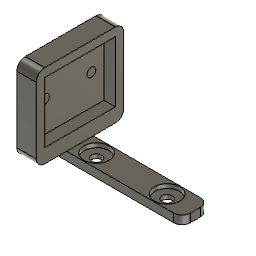
cctvAqara (Autodesk Fusion 360 design; units mm, degrees)
part number: 2026-08-10-19-56-16-923
Autodesk Fusion 360 part; units mm, degrees
sketch "Sketch1" plane through (0, 0, 0) normal (0, 0, 1) x (1, 0, 0)
  line L0 (-28, 37) -> (62, 37)
  line L1 (62, 37) -> (62, 18)
  line L2 (62, 18) -> (-28, 18)
  line L3 (-28, 18) -> (-28, 37)
  dimension "d1" = 90
  dimension "d2" = 19
  constraint horizontal L0
  constraint vertical L1
  constraint horizontal L2
  constraint vertical L3
  measures "d1" distance of L0.start L0.end
  measures "d2" distance of L0.start L2.end
extrude "Extrude1" add sketch "Sketch1" along normal blind 6 makes body 1
sketch "Sketch2" plane through (0, 0, 6) normal (0, 0, 1) x (-1, 0, 0)
  line L0 (28, -37) -> (28, -18)
  line L1 (28, -18) -> (-62, -18)
  line L2 (-62, -18) -> (-62, -37)
  line L3 (-62, -37) -> (28, -37)
ref_plane "WorkPlane1" through (17, 27.5, 6) normal (0, 0, 1) x (-1, 0, 0)
sketch "Sketch3" plane through (0, 0, 6) normal (0, 0, 1) x (1, 0, 0)
  line L0 (17, 37) -> (17, 18)
  circle A0 centre (-8, 27.5) radius 8.9
  circle A1 centre (42, 27.5) radius 8.9
  circle A2 centre (-8, 27.5) radius 3.65
  circle A3 centre (42, 27.5) radius 3.65
  dimension "d13" = 17.8
  dimension "d14" = 17.8
  dimension "d15" = 7.3
  dimension "d16" = 7.3
  constraint vertical L0
  constraint concentric A0 A2
  constraint concentric A1 A3
  measures "d13" diameter of A0
  measures "d14" diameter of A1
  measures "d15" diameter of A2
  measures "d16" diameter of A3
extrude "Extrude2" cut sketch "Sketch3" against normal blind 7 contours A2 | A3 bodies 1
extrude "Extrude3" cut sketch "Sketch3" against normal blind 3 bodies 1
sketch "Sketch4" plane through (0, 0, 0) normal (0, 0, 1) x (1, 0, 0)
  line L0 (-21, 37) -> (55, 37)
  line L1 (55, 37) -> (55, 39)
  line L2 (55, 39) -> (-21, 39)
  line L3 (-21, 39) -> (-21, 37)
  dimension "d21" = 76
  dimension "d22" = 2
  constraint horizontal L0
  constraint vertical L1
  constraint horizontal L2
  constraint vertical L3
  measures "d21" distance of L0.start L0.end
  measures "d22" distance of L0.start L2.end
sketch "Sketch7" plane through (-28, 0, 0) normal (-1, 0, 0) x (0, -1, 0)
  line L0 (-37, 0) -> (-18, 0)
  line L1 (-18, 0) -> (-18, 6)
  line L2 (-18, 6) -> (-37, 6)
  line L3 (-37, 6) -> (-37, 0)
  line L4 (-37, 6) -> (-58.5, 6)
  line L5 (-58.5, 6) -> (-58.5, 65)
  line L6 (-58.5, 65) -> (-37, 65)
  line L7 (-58.5, 65) -> (3.5, 65)
  line L8 (3.5, 65) -> (3.5, 6)
  line L9 (3.5, 6) -> (-58.5, 6)
  line L10 (-58.5, 6) -> (-58.5, 65)
  dimension "d37" = 21.5
  dimension "d38" = 59
  dimension "d39" = 62
  dimension "d40" = 59
  constraint horizontal L4
  constraint vertical L5
  constraint horizontal L6
  constraint coincident L2.end L3.start
  constraint horizontal L7
  constraint vertical L8
  constraint horizontal L9
  constraint vertical L10
  measures "d37" distance of L2.end L4.end
  measures "d38" distance of L2.end L6.end
  measures "d39" distance of L5.end L7.end
  measures "d40" distance of L5.end L4.end
extrude "Extrude7" add sketch "Sketch7" along normal blind 5.55 separate body contours L2 L4 L5 L6 L7 L8 L9 L10 makes body 2
extrude "Extrude8" add 1 faces at (-28, 24.3333, 4) along direction (-1, 0, 0) blind 5.55 on bodies 1 bodies 1 2
sketch "Sketch8" plane through (-28, 0, 0) normal (1, 0, 0) x (0, 1, 0)
  line L0 (-3.5, 6) -> (18, 6)
  line L1 (18, 6) -> (37, 6)
  line L2 (37, 6) -> (58.5, 6)
  line L3 (58.5, 6) -> (58.5, 65)
  line L4 (58.5, 65) -> (-3.5, 65)
  line L5 (-3.5, 65) -> (-3.5, 6)
  line L6 (-3.5, 6) -> (58.5, 6)
  line L7 (58.5, 6) -> (58.5, 16)
  line L8 (58.5, 16) -> (-3.5, 16)
  line L9 (-3.5, 16) -> (-3.5, 6)
  dimension "d45" = 62
  dimension "d46" = 10
  constraint horizontal L6
  constraint vertical L7
  constraint horizontal L8
  constraint vertical L9
  constraint coincident L0.start L5.end
  measures "d45" distance of L0.start L2.end
  measures "d46" distance of L0.start L8.end
extrude "Extrude9" add sketch "Sketch8" along normal blind 8.3 contours L0 L1 L2 L3 L5 L6 L7 L8 L9 bodies 1
sketch "Sketch9" plane through (0, 0, 0) normal (1, 0, 0) x (0, 1, 0)
ref_plane "WorkPlane3" through (-28, 27.5, 40.5) normal (1, 0, 0) x (0, 1, 0)
sketch "Sketch10" plane through (-28, 0, 0) normal (1, 0, 0) x (0, 1, 0)
  line L0 (58.5, 65) -> (52.5, 65)
  line L1 (52.5, 65) -> (52.5, 16)
  line L2 (52.5, 16) -> (58.5, 16)
  line L3 (58.5, 16) -> (58.5, 65)
  line L4 (-3.5, 65) -> (2.5, 65)
  line L5 (2.5, 65) -> (2.5, 16)
  line L6 (2.5, 16) -> (-3.5, 16)
  line L7 (-3.5, 16) -> (-3.5, 65)
  line L8 (2.5, 65) -> (52.5, 65)
  line L9 (52.5, 65) -> (52.5, 59)
  line L10 (52.5, 59) -> (2.5, 59)
  line L11 (2.5, 59) -> (2.5, 65)
  dimension "d50" = 6
  dimension "d51" = 49
  dimension "d52" = 6
  dimension "d53" = 49
  dimension "d54" = 50
  dimension "d55" = 6
  constraint horizontal L0
  constraint vertical L1
  constraint horizontal L2
  constraint vertical L3
  constraint horizontal L4
  constraint vertical L5
  constraint horizontal L6
  constraint vertical L7
  constraint horizontal L8
  constraint vertical L9
  constraint horizontal L10
  constraint vertical L11
  measures "d50" distance of L0.start L0.end
  measures "d51" distance of L0.start L2.end
  measures "d52" distance of L4.start L4.end
  measures "d53" distance of L4.start L6.end
  measures "d54" distance of L4.end L0.end
  measures "d55" distance of L4.end L10.end
extrude "Extrude10" add sketch "Sketch10" along normal blind 8.3 bodies 1
sketch "Sketch11" plane through (-28, 0, 0) normal (1, 0, 0) x (0, 1, 0)
  line L0 (2.5, 59) -> (2.5, 16)
  line L1 (2.5, 16) -> (52.5, 16)
  line L2 (52.5, 16) -> (52.5, 59)
  line L3 (52.5, 59) -> (2.5, 59)
  line L4 (2.5, 16) -> (2.5, 34.3)
  line L5 (2.5, 34.3) -> (2.5, 37.4)
  line L6 (2.5, 37.4) -> (8.1, 37.4)
  line L7 (8.1, 37.4) -> (11.2, 37.4)
  circle A0 centre (11.2, 37.4) radius 3.1
  line L8 (11.2, 37.4) -> (43.8, 37.4)
  circle A1 centre (43.8, 37.4) radius 3.1
  dimension "d58" = 18.3
  dimension "d59" = 3.1
  dimension "d60" = 5.6
  dimension "d61" = 3.1
  dimension "d62" = 6.2
  dimension "d63" = 32.6
  dimension "d64" = 6.2
  constraint coincident L0.end L1.start
  constraint perpendicular L1 L4
  constraint parallel L0 L5
  constraint perpendicular L5 L6
  constraint perpendicular L0 L7
  constraint coincident L7.end A0.centre
  constraint perpendicular L0 L8
  constraint coincident L8.end A1.centre
  measures "d58" distance of L0.end L4.end
  measures "d59" distance of L4.end L5.end
  measures "d60" distance of L5.end L6.end
  measures "d61" distance of L6.end L7.end
  measures "d62" diameter of A0
  measures "d63" distance of L7.end L8.end
  measures "d64" diameter of A1
extrude "Extrude11" cut sketch "Sketch11" against normal blind 3.15 contours L7 A0 L8 | L7 A0 L8 | A1 bodies 1
sketch "Sketch12" plane through (-28, 0, 0) normal (1, 0, 0) x (0, 1, 0)
  circle A0 centre (11.2, 37.4) radius 3.1
  circle A1 centre (43.8, 37.4) radius 3.1
  line L0 (2.5, 59) -> (2.5, 16)
  line L1 (2.5, 16) -> (52.5, 16)
  line L2 (52.5, 16) -> (52.5, 59)
  line L3 (52.5, 59) -> (2.5, 59)
  line L4 (2.5, 59) -> (52.5, 59)
  line L5 (52.5, 59) -> (52.5, 16)
  line L6 (52.5, 16) -> (2.5, 16)
  line L7 (2.5, 16) -> (2.5, 59)
  constraint horizontal L4
  constraint vertical L5
  constraint horizontal L6
  constraint vertical L7
  constraint coincident L1.end L2.start
  constraint coincident L0.start L3.end
extrude "Extrude12" add sketch "Sketch12" along normal blind 0.2 contours A0 | A1 | L0 L1 L2 L3 L4 L5 L6 L7 bodies 1
fillet "Fillet3" radius 6 6 edges at (-26.625, 58.5, 6) (-26.625, 58.5, 65) (-23.85, -3.5, 65) (-30.775, -3.5, 65) (-23.85, -3.5, 65) (-30.775, -3.5, 65) on bodies 1
fillet "Fillet4" radius 6 1 edges at (-26.625, -3.5, 6) on bodies 1
fillet "Fillet5" radius 6 2 edges at (62, 18, 3) (62, 37, 3) on bodies 1
